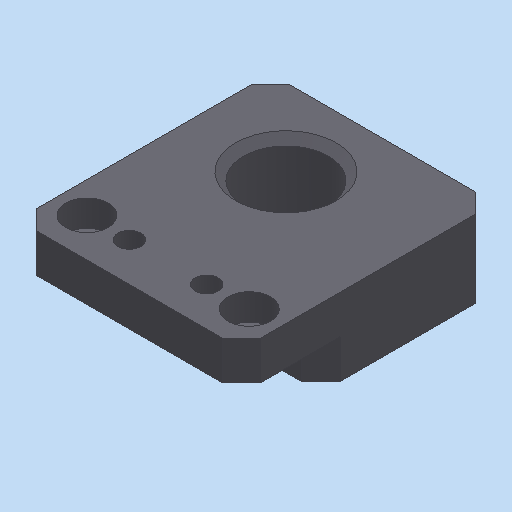
# Autodesk Inventor part: MM0869AN120_G01_141
Saved by Autodesk Inventor 2023.3 (Build 273359000, 359)
## iProperties
Part Number: MM0869AN120_G01_141
Project: 0850
Material: 1.2379 X155CrVMo12-1
Description: =<RBPARTNOTITLE2>
Document SubType Name: Modeling
Designer: FH/Da
Density: 7.85 g/cm^3
Appearance: grau AnP
Mass: 416.97 g
Surface Area: 129.939 cm^2
Volume: 53.1172 cm^3
RBDOCUMENTTYPE: DRF
RBDOCUMENTVERSION: 00
RBDRAWINGMAINSCALE: 1:1
RBDRAWINGMISSINGSPEC: --
RBDRAWINGVOLUME: --
RBGBEDGESIN1: +0,5
RBGBEDGESIN2: +0,2
RBGBEDGESOUT1: -0,3
RBGBEDGESOUT2: -0,1
RBMATERIAL: =<Material>
RBMATMEETS: --
RBMATNO: =<Part Number>
RBPARTMADEOF: 20 x 65,5 x 58 (FM)
RBPARTNO: SIEHE MNR
RBPARTNOTITLE1: manufactured part
RBPARTNOTITLE2: Anfertigungsteil
RBPARTSAFETYINDICATOR: --
RBSURFACE: Dylyn DLC coated
RBSURFACE2: Dylyn DLC beschichtet
RBZEDGESNORM: ISO13715:2002-06
RBZGENDIMCLASS: m
RBZGENDIMNORM: ISO 2768-1:1989-11
RBZGENGEOCLASS: H
RBZGENGEONORM: ISO 2768-2:1989-11
RBZSURFACENORM: ISO13D2:2002-02
RBZTOLERANCENORM: ISO 14405-1:2010-12
RBSURFACE12: and hardened 60 HRC ± 1
RBSURFACE22: und gehaertet 60 HRC ± 1
AnP_Material: =<Material>
AnP_TemplVers: 20190222
AnP_Kategorie: 1
MaxAbmaße: 20 x 65,5 x 58 (FM)
Name: MM0868AN110_G04_107.ipt
Author: FH/Da
Keywords: =<RBPARTMADEOF>
Comments: =<RBSURFACE2>
Revision Number: 01
Autodesk Inventor part; units mm, degrees
ref_plane "YZ Plane" through (0, 0, 0) normal (1, 0, 0) x (0, 1, 0)
ref_plane "XZ Plane" through (0, 0, 0) normal (0, 1, 0) x (-1, 0, 0)
ref_plane "XY Plane" through (0, 0, 0) normal (0, 0, 1) x (1, 0, 0)
sketch "Skizze1" plane through (0, 0, 0) normal (0, 0, 1) x (1, 0, 0)
  line L0 (-29, 65.5) -> (29, 65.5)
  line L1 (29, 65.5) -> (29, 0)
  line L2 (29, 0) -> (-29, 0)
  line L3 (-29, 0) -> (-29, 65.5)
  point P0 (0, 0)
  point P1 (0, 0)
  dimension "d0" = 58
  dimension "d1" = 65.5
  constraints: 8 end point, 2 parallel, 1 coincident, 1 horizontal, 1 midpoint, 1 perpendicular
  measures "d0" distance between parallel lines of L1 L3
  measures "d1" distance between parallel lines of L2 L0
extrude "Extrusion1" add sketch "Skizze1" along normal blind 20
sketch "Skizze2" plane through (0, 0, 20) normal (0, 0, 1) x (1, 0, 0)
  line L0 (-29, 0) -> (29, 0) projected
  line L1 (29, 65.5) -> (29, 0) projected
  line L2 (-29, 65.5) -> (-29, 0) projected
  point P0 (21, 10)
  point P1 (-21, 10)
  dimension "d48" = 10
  dimension "d49" = 8
  dimension "d50" = 8
  constraints: 1 horizontal alignment
  measures "d48" distance from line of L0 point (21, 10)
  measures "d49" distance from line of L1 point (21, 10)
  measures "d50" distance from line of L2 point (-21, 10)
hole "Bohrung1" at (21, 10, 20) at (-21, 10, 20) direction (0, 0, -1) diameter 6.6 end through all counterbore diameter 11 counterbore depth 6.8 clearance for "Inbusschraube ISO 4762  versenkt" size "M6" standard "ISO"
sketch "Skizze3" plane through (0, 0, 20) normal (0, 0, 1) x (1, 0, 0)
  circle A0 centre (-21, 10) radius 3.3 projected
  circle A1 centre (21, 10) radius 3.3 projected
  point P0 (10, 10)
  point P1 (-10, 10)
  dimension "d51" = 11
  dimension "d52" = 11
  constraints: 2 horizontal alignment
  measures "d51" distance of point (-10, 10) A0.centre
  measures "d52" distance of A1.centre point (10, 10)
hole "Bohrung2" at (10, 10, 20) at (-10, 10, 20) direction (0, 0, -1) diameter 6 end through all
sketch "Skizze4" plane through (0, 0, 20) normal (0, 0, 1) x (1, 0, 0)
  line L0 (-29, 65.5) -> (29, 65.5) projected
  line L1 (-29, 65.5) -> (-29, 0) projected
  point P0 (0, 0)
  point P1 (-5, 45.5)
  dimension "d46" = 20
  dimension "d47" = 24
  measures "d46" distance from line of L0 point (-5, 45.5)
  measures "d47" distance from line of point (-5, 45.5) L1
hole "Bohrung3" at (-5, 45.5, 20) direction (0, 0, -1) diameter 22 end through all
sketch "Skizze5" plane through (29, 0, 0) normal (1, 0, 0) x (0, 0, -1)
  line L0 (0, 0) -> (-20, 0) projected
  line L1 (0, 65.5) -> (0, 0) projected
  line L2 (0, 0) -> (-10, 0)
  line L3 (-10, 0) -> (-10, 20.5)
  line L4 (-10, 20.5) -> (0, 20.5)
  line L5 (0, 20.5) -> (0, 0)
  line L6 (-20, 0) -> (-20, 65.5) projected
  dimension "d53" = 10
  dimension "d54" = 20.5
  constraints: 8 end point, 2 parallel, 1 horizontal, 1 perpendicular
  measures "d53" distance between parallel lines of L3 L6
  measures "d54" distance between parallel lines of L4 L0
extrude "Extrusion2" cut sketch "Skizze5" against normal through all
chamfer "Fase2" distance 2 angle 45 2 edges at (-5, 56.5, 20) (-5, 56.5, 0)
chamfer "Fase4" distance 5 angle 45 6 edges at (29, 65.5, 10) (-29, 65.5, 10) (29, 0, 15) (-29, 0, 15) (-29, 20.5, 5) (29, 20.5, 5)
equation "\"d50\" = d49"
equation "\"d52\" = d51"
